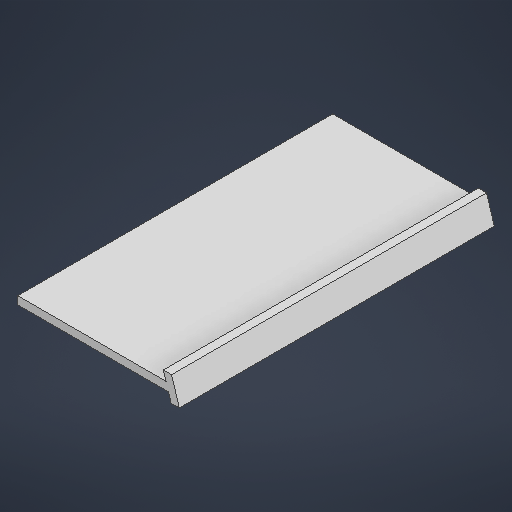
# Autodesk Inventor part: top
Saved by Autodesk Inventor 2026.1 (Build 301233020, 233B)
## iProperties
Created: 2026-04-17
Part Number: top
Material: Generic
Document SubType Name: Modeling
Designer: runek
Density: 1 g/cm^3
Appearance: Default
Author: runek
Autodesk Inventor part; units mm, degrees
ref_plane "YZ Plane" through (0, 0, 0) normal (1, 0, 0) x (0, 1, 0)
ref_plane "XZ Plane" through (0, 0, 0) normal (0, 1, 0) x (-1, 0, 0)
ref_plane "XY Plane" through (0, 0, 0) normal (0, 0, 1) x (1, 0, 0)
sketch "Sketch1" plane through (0, 0, 0) normal (0, 1, 0) x (-1, 0, 0)
  line L0 (0, 0) -> (0, 153.55)
  line L1 (0, 153.55) -> (75, 153.55)
  line L2 (75, 153.55) -> (75, 0)
  line L3 (75, 0) -> (0, 0)
  line L4 (0, 0) -> (4, 0)
  line L5 (4, 0) -> (4, 153.55)
  dimension "d0" = 153.55
  dimension "d1" = 75
  dimension "d2" = 4
  constraints: 12 end point, 2 parallel, 2 perpendicular, 2 point on line, 1 vertical
  measures "d0" distance of L0.start L0.end
  measures "d1" distance of L0.end L1.end
  measures "d2" distance of L0.start L4.end
extrude "Extrusion1" add sketch "Sketch1" along normal blind 3.85 contours L5 L1 L2 L3
extrude "Extrusion2" add sketch "Sketch1" along normal blind 8 contours L0 L1 L5 L3
extrude "Extrusion3" add sketch "Sketch1" against normal blind 4.15 contours L0 L1 L5 L3
sketch "Sketch2" plane through (-75, 0, 153.55) normal (0, 0, 1) x (1, 0, 0)
  line L0 (71, 0) -> (0, 0) projected
  line L1 (71, 0) -> (74.0483, -4.15)
  line L2 (71, -4.15) -> (75, -4.15) projected
  line L3 (71, 0) -> (71, -4.15) projected
  line L4 (71, 0) -> (71, -4.15)
  line L5 (71, -4.15) -> (74.0483, -4.15)
  point P0 (75, 0)
  constraints: 6 end point, 1 collinear, 1 point on line
extrude "Extrusion4" cut sketch "Sketch2" against normal blind 200
sketch "Sketch3" plane through (-75, 0, 153.55) normal (0, 0, 1) x (1, 0, 0)
  line L0 (71, 3.85) -> (71, 8) projected
  line L1 (71, 8) -> (75, -4.906)
  line L2 (71, 8) -> (84.5116, 8) construction
  line L3 (71, 8) -> (75, 8) projected
  line L4 (71, 8) -> (75, 8)
  line L5 (75, 8) -> (75, -3.855)
  line L6 (75, -3.855) -> (75, -4.906)
  line L7 (71, 0) -> (74.0483, -4.15) projected
  line L8 (71, 0) -> (73.4795, 0)
  line L9 (74.0483, -4.15) -> (74.0483, -4.15)
  line L10 (71, 8) -> (71, 3.85)
  line L11 (0, 3.85) -> (71, 3.85) projected
  line L12 (71, 3.85) -> (72.2862, 3.85)
  line L13 (74.0483, -4.15) -> (74.7657, -4.15)
  line L14 (75, -4.15) -> (74.0483, -4.15) projected
  point P0 (75, 0)
  dimension "d11" = 72.78
  constraints: 20 end point, 4 collinear, 4 point on line, 2 horizontal, 1 equal length, 1 perpendicular
  measures "d11" angle of L1 L2
extrude "Extrusion5" cut sketch "Sketch3" against normal blind 200 contours L0 L1 L12 | L1 L13 L7 L8
sketch "Sketch4" plane through (0, 8, 153.55) normal (1, 0, 0) x (0, 0, -1)
  point P0 (153.55, -8)
sketch "Sketch5" plane through (-75, 0, 153.55) normal (0, 0, 1) x (1, 0, 0)
  line L0 (75, -4.15) -> (75, 8) projected
  line L1 (75, 8) -> (78.7657, -4.15)
  line L2 (75, 8) -> (87.7202, 8) construction
  line L3 (78.7657, -4.15) -> (75, -4.15)
  line L4 (75, -4.15) -> (75, 8)
  point P0 (75, 0)
  dimension "d14" = 72.78
  constraints: 8 end point, 2 perpendicular, 1 equal length, 1 horizontal
  measures "d14" angle of L1 L2
extrude "Extrusion6" add sketch "Sketch5" against normal blind 153.55
body "Solid1"
